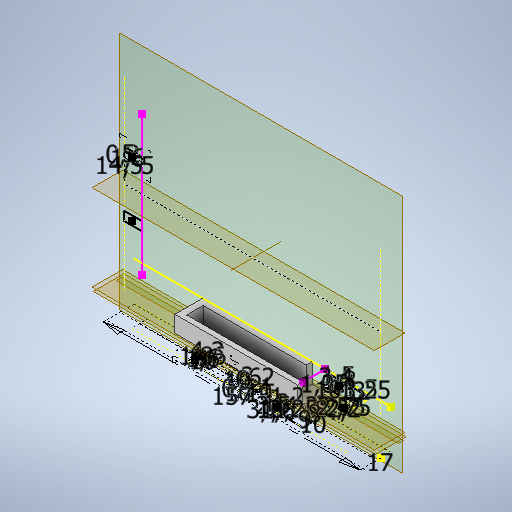
# Autodesk Inventor part: up_part
Saved by Autodesk Inventor 2025 (Build 290162000, 162)
## iProperties
Created: 2026-07-31
Part Number: up_part
Material: Типовые
Document SubType Name: Modeling
Designer: garin
Density: 1 g/cm^3
Appearance: По умолчанию
Author: garin
Autodesk Inventor part; units mm, degrees
ref_plane "YZ Plane" through (0, 0, 0) normal (1, 0, 0) x (0, 1, 0)
ref_plane "XZ Plane" through (0, 0, 0) normal (0, 1, 0) x (-1, 0, 0)
ref_plane "XY Plane" through (0, 0, 0) normal (0, 0, 1) x (1, 0, 0)
sketch "Эскиз1" plane through (0, 0, 0) normal (0, 0, 1) x (1, 0, 0)
  line L0 (0, 0) -> (-157, 0)
  line L1 (-157, 0) -> (-157, 133.4)
  line L2 (-157, 133.4) -> (0, 133.4)
  line L3 (0, 133.4) -> (0, 0)
  line L4 (-157, 66.7) -> (0, 66.7) construction
  line L5 (-78.5, 0) -> (-78.5, 133.4) construction
  line L6 (-11, 24.1) -> (-146, 24.1)
  line L7 (-146, 24.1) -> (-146, 109.3)
  line L8 (-146, 109.3) -> (-11, 109.3)
  line L9 (-11, 109.3) -> (-11, 24.1)
  line L10 (-11, 24.1) -> (-146, 109.3) construction
  line L11 (-146, 24.1) -> (-11, 109.3) construction
  line L12 (0, 0) -> (-2, 0) construction
  line L13 (-2, 0) -> (-2, 54.105) construction
  line L14 (-2, 54.105) -> (0, 54.105) construction
  line L15 (0, 54.105) -> (0, 0) construction
  line L16 (-2, 54.105) -> (-2, 74.935)
  line L17 (-2, 74.935) -> (-11, 74.935)
  line L18 (-2, 54.105) -> (-11, 54.105)
  line L19 (-157, 133.4) -> (-137, 133.4) construction
  line L20 (-157, 110.4) -> (-157, 133.4) construction
  line L21 (-157, 0) -> (-140, 0)
  line L22 (-140, 0) -> (-140, 22)
  line L23 (-140, 22) -> (-157, 22)
  line L24 (-157, 22) -> (-157, 0)
  line L25 (-157, 0) -> (-140, 0)
  line L26 (-140, 0) -> (-140, 6.5)
  line L27 (-140, 6.5) -> (-157, 6.5)
  line L28 (-157, 6.5) -> (-157, 0)
  line L29 (-140, 133.4) -> (-140, 111.4)
  line L30 (-140, 111.4) -> (-157, 111.4)
  line L31 (-140, 126.9) -> (-157, 126.9)
  line L32 (-17, 0) -> (-17, 22)
  line L33 (-17, 22) -> (0, 22)
  line L34 (-17, 6.5) -> (0, 6.5)
  line L35 (-17, 111.4) -> (0, 111.4)
  line L36 (-17, 126.9) -> (0, 126.9)
  line L37 (-17, 133.4) -> (-17, 111.4)
  line L38 (-146, 109.3) -> (-149, 109.3)
  line L39 (-149, 109.3) -> (-149, 24.1)
  line L40 (-149, 24.1) -> (-146, 24.1)
  line L41 (-146, 24.1) -> (-146, 109.3)
  point P0 (-78.5, 66.7)
  point P1 (0, 111.4)
  point P2 (0, 126.9)
  point P3 (-17, 126.9)
  point P4 (-140, 126.9)
  point P5 (0, 6.5)
  dimension "d0" = 157
  dimension "d1" = 133.4
  dimension "d2" = 135
  dimension "d3" = 85.2
  dimension "d20" = 2
  dimension "d21" = 54.105
  dimension "d22" = 20.83
  dimension "d75" = 17
  dimension "d76" = 22
  dimension "d77" = 17
  dimension "d78" = 6.5
  dimension "d151" = 3
  dimension "d152" = 85.2
  constraints: 84 end point, 15 symmetric about line, 12 parallel, 8 perpendicular, 7 horizontal, 7 midpoint, 2 point on line, 1 vertical
  measures "d0" distance of L1.end L2.end
  measures "d1" distance of L0.end L1.end
  measures "d2" distance of L7.end L8.end
  measures "d3" distance of L6.end L7.end
  measures "d20" distance of L13.end L14.end
  measures "d21" distance of L12.end L13.end
  measures "d22" distance of L13.end L16.end
  measures "d75" distance of L23.end L22.end
  measures "d76" distance of L22.end L21.end
  measures "d77" distance of L27.end L26.end
  measures "d78" distance of L26.end L25.end
  measures "d151" distance of L40.end L39.end
  measures "d152" distance of L39.end L38.end
extrude "Выдавливание1" add sketch "Эскиз1" along normal blind 17 contours L0 L32 L34 L3 | L0 L22 L23 L1 L30 L29 L2 L37 L35 L3 L33 L32 | L34 L32 L33 L3 | L0 L1 L27 L22 | L27 L1 L23 L22 | L35 L37 L36 L3 | L36 L37 L2 L3 | L1 L31 L29 L30 | L1 L2 L29 L31 | L9 L17 L16 L18
chamfer "Фаска1" distance 14 angle 45 2 edges at (-78.5, 0, 17) (-78.5, 133.4, 17)
chamfer "Фаска2" distance 5 angle 45 2 edges at (-157, 66.7, 17) (0, 66.7, 17)
sketch "Эскиз2" plane through (-157, 0, 3) normal (0, -0.7071068, 0.7071068) x (1, 0, 0)
  line L0 (0, -2.1213) -> (157, -2.1213) projected
  line L1 (0, -2.1213) -> (157, -2.1213)
  line L2 (157, -2.1213) -> (157, 18.3787)
  line L3 (157, 18.3787) -> (0, 18.3787)
  line L4 (0, 18.3787) -> (0, -2.1213)
  line L5 (78.5, 18.3787) -> (78.5, -2.1213) construction
  line L6 (0, 8.1287) -> (157, 8.1287) construction
  line L7 (154, 1.1287) -> (3, 1.1287) construction
  line L8 (3, 1.1287) -> (3, 15.1287) construction
  line L9 (3, 15.1287) -> (154, 15.1287) construction
  line L10 (154, 15.1287) -> (154, 1.1287) construction
  line L11 (154, 1.1287) -> (3, 15.1287) construction
  line L12 (3, 1.1287) -> (154, 15.1287) construction
  line L13 (3, 15.1287) -> (12, 15.1287) construction
  line L14 (12, 15.1287) -> (3, 2.4008)
  line L15 (0, 12.7279) -> (5, 19.799) construction
  line L16 (145, 15.1287) -> (154, 2.4008)
  line L17 (12, 15.1287) -> (145, 15.1287)
  line L18 (11, 14.92) -> (11, 26.9408) projected
  line L19 (154, 2.4008) -> (154, 1.1287)
  line L20 (154, 1.1287) -> (3, 1.1287)
  line L21 (3, 2.4008) -> (3, 1.1287)
  line L22 (5.9642, 3.1287) -> (13.0353, 13.1287)
  line L23 (13.0353, 13.1287) -> (143.9647, 13.1287)
  line L24 (143.9647, 13.1287) -> (151.0358, 3.1287)
  line L25 (151.0358, 3.1287) -> (5.9642, 3.1287)
  point P0 (78.5, 8.1287)
  dimension "d12" = 157
  dimension "d13" = 20.5
  dimension "d14" = 151
  dimension "d15" = 14
  dimension "d16" = 9
  dimension "d17" = 2
  constraints: 46 end point, 7 midpoint, 5 parallel, 5 perpendicular, 2 horizontal, 2 point on line, 2 symmetric about line, 1 collinear, 3 other
  measures "d12" distance of L3.end L2.end
  measures "d13" distance of L2.end L1.end
  measures "d14" distance of L8.end L9.end
  measures "d15" distance of L7.end L8.end
  measures "d16" distance of L8.end L13.end
  measures "d17" distance between parallel lines of L14 L22
extrude "Выдавливание2" cut sketch "Эскиз2" against normal blind 1 contours L17 L16 L19 L20 L21 L14
ref_plane "РабПлоскость1" through (-157, 66.7, 0) normal (0, 1, 0) x (1, 0, 0)
mirror "Зеркальное отражение1" about plane through (-157, 66.7, 0) normal (0, 1, 0) of "Выдавливание2"
extrude "Выдавливание3" cut sketch "Эскиз1" along normal blind 11.1 contours L9 L17 L16 L18
sketch "Эскиз3" plane through (-157, 0, 0) normal (0, -1, 0) x (1, 0, 0)
  line L0 (0, 0) -> (157, 0) construction
  line L1 (0, 0) -> (157, 0) construction
  line L2 (157, 0) -> (157, 17) construction
  line L3 (157, 17) -> (0, 17) construction
  line L4 (0, 17) -> (0, 0) construction
  line L5 (78.5, 17) -> (78.5, 0) construction
  line L6 (0, 8.5) -> (157, 8.5) construction
  line L7 (145, 13.6976) -> (12, 13.6976) construction
  line L8 (12, 13.6976) -> (12, 3.7981) construction
  line L9 (3, 3.7981) -> (154, 3.7981) construction
  line L10 (12, 8.7478) -> (78.5, 8.7478) construction
  line L11 (12, 8.7478) -> (78.5, 8.7478) construction
  line L12 (83.5, 3.7478) -> (73.5, 3.7478)
  line L13 (73.5, 3.7478) -> (73.5, 13.7478)
  line L14 (73.5, 13.7478) -> (83.5, 13.7478)
  line L15 (83.5, 13.7478) -> (83.5, 3.7478)
  line L16 (83.5, 3.7478) -> (73.5, 13.7478) construction
  line L17 (73.5, 3.7478) -> (83.5, 13.7478) construction
  line L18 (46.5, 13.2478) -> (108.5, 13.2478) construction
  line L19 (108.5, 13.2478) -> (108.5, 4.2478) construction
  line L20 (108.5, 4.2478) -> (46.5, 4.2478) construction
  line L21 (46.5, 4.2478) -> (46.5, 13.2478) construction
  line L22 (46.5, 13.2478) -> (108.5, 4.2478) construction
  line L23 (108.5, 13.2478) -> (46.5, 4.2478) construction
  line L24 (109, 13.7478) -> (46, 13.7478)
  line L25 (46, 13.7478) -> (46, 3.7478)
  line L26 (46, 3.7478) -> (109, 3.7478)
  line L27 (109, 3.7478) -> (109, 13.7478)
  line L28 (46.5, 8.7478) -> (48.3, 8.7478) construction
  line L29 (48.3, 6.7478) -> (48.3, 10.7478) construction
  circle A0 centre (48.3, 10.7478) radius 0.8
  circle A1 centre (48.3, 6.7478) radius 0.8
  line L30 (109, 13.7478) -> (117, 13.7478)
  line L31 (117, 13.7478) -> (117, 3.7478)
  line L32 (117, 3.7478) -> (109, 3.7478)
  line L33 (109, 3.7478) -> (109, 13.7478)
  line L34 (108.5, 13.2478) -> (98.25, 13.2478) construction
  line L35 (98.25, 13.2478) -> (98.25, 10.7478) construction
  line L36 (98.25, 10.7478) -> (108.5, 10.7478) construction
  line L37 (108.5, 10.7478) -> (108.5, 13.2478) construction
  circle A2 centre (98.25, 10.7478) radius 0.8
  line L38 (78.5, 8.7478) -> (77.5, 8.7478) construction
  line L39 (97.45, 10.7478) -> (97.45, 13.7478) construction
  line L40 (97.45, 13.7478) -> (96.25, 13.7478) construction
  line L41 (96.25, 13.7478) -> (96.25, 3.7478)
  line L42 (96.25, 3.7478) -> (97.45, 3.7478) construction
  line L43 (97.45, 3.7478) -> (97.45, 13.7478) construction
  line L44 (83.5, 13.7478) -> (84.5, 13.7478) construction
  line L45 (84.5, 13.7478) -> (84.5, 3.7478)
  line L46 (84.5, 3.7478) -> (83.5, 3.7478) construction
  line L47 (83.5, 3.7478) -> (83.5, 13.7478) construction
  line L48 (73.5, 13.7478) -> (71.5, 13.7478) construction
  line L49 (71.5, 13.7478) -> (71.5, 3.7478)
  line L50 (71.5, 3.7478) -> (73.5, 3.7478) construction
  line L51 (73.5, 3.7478) -> (73.5, 13.7478) construction
  line L52 (46, 13.7478) -> (50.3, 13.7478) construction
  line L53 (50.3, 13.7478) -> (50.3, 3.7478)
  line L54 (50.3, 3.7478) -> (46, 3.7478) construction
  line L55 (46, 3.7478) -> (46, 13.7478) construction
  line L56 (117, 3.7478) -> (109, 3.7478)
  line L57 (109, 3.7478) -> (109, -0.5022)
  line L58 (109, -0.5022) -> (117, -0.5022)
  line L59 (117, -0.5022) -> (117, 3.7478)
  line L60 (99.05, 10.7478) -> (99.05, 13.2478) construction
  line L61 (99.05, 13.2478) -> (100.25, 13.2478) construction
  line L62 (100.25, 13.2478) -> (100.25, 3.7478)
  circle A3 centre (98.25, 10.7478) radius 1.6
  line L63 (99.85, 10.7478) -> (99.85, 13.7478)
  line L64 (96.65, 10.7478) -> (96.65, 13.7478)
  line L65 (100.25, 13.2478) -> (100.25, 13.7478)
  point P0 (84.5, 13.7478)
  point P1 (84.5, 3.7478)
  point P2 (96.25, 3.7478)
  point P3 (96.25, 13.7478)
  point P4 (50.3, 3.7478)
  point P5 (71.5, 3.7478)
  point P6 (71.5, 13.7478)
  point P7 (96.65, 13.7478)
  point P8 (73.5, 3.7478)
  point P9 (83.5, 3.7478)
  dimension "d25" = 157
  dimension "d26" = 17
  dimension "d28" = 10
  dimension "d29" = 10
  dimension "d30" = 62
  dimension "d31" = 9
  dimension "d32" = 0.5
  dimension "d33" = 1.8
  dimension "d34" = 4
  dimension "d35" = 1.6
  dimension "d36" = 1.6
  dimension "d37" = 8
  dimension "d38" = 10
  dimension "d39" = 10.25
  dimension "d40" = 2.5
  dimension "d41" = 1.6
  dimension "d42" = 1
  dimension "d44" = 1.2
  dimension "d45" = 10
  dimension "d46" = 1
  dimension "d47" = 10
  dimension "d48" = 2
  dimension "d49" = 10
  dimension "d50" = 4.3
  dimension "d51" = 10
  dimension "d63" = 8
  dimension "d64" = 4.25
  dimension "d210" = 1.2
  dimension "d211" = 3.2
  constraints: 126 end point, 23 parallel, 17 point on line, 16 perpendicular, 12 horizontal, 11 midpoint, 4 centre point, 4 coincident, 4 point on circle, 4 tangent, 2 vertical, 1 collinear, 3 other
  measures "d25" distance of L3.end L2.end
  measures "d26" distance of L2.end L1.end
  measures "d28" distance of L13.end L14.end
  measures "d29" distance of L12.end L13.end
  measures "d30" distance of L19.end L20.end
  measures "d31" distance of L18.end L19.end
  measures "d32" distance between parallel lines of L18 L24
  measures "d33" distance of L28.end L28.start
  measures "d34" distance of L29.start L29.end
  measures "d35" diameter of A0
  measures "d36" diameter of A1
  measures "d37" distance of L31.end L32.end
  measures "d38" distance of L30.end L31.end
  measures "d39" distance of L36.end L35.end
  measures "d40" distance of L35.end L34.end
  measures "d41" diameter of A2
  measures "d42" distance of L11.end L38.end
  measures "d44" distance of L42.end L41.end
  measures "d45" distance of L41.end L40.end
  measures "d46" distance of L45.end L46.end
  measures "d47" distance of L44.end L45.end
  measures "d48" distance of L50.end L49.end
  measures "d49" distance of L49.end L48.end
  measures "d50" distance of L53.end L54.end
  measures "d51" distance of L52.end L53.end
  measures "d63" distance of L58.end L57.end
  measures "d64" distance of L57.end L56.end
  measures "d210" distance of L60.end L61.end
  measures "d211" diameter of A3
extrude "Выдавливание4" cut sketch "Эскиз3" along normal blind 25 from surface at -24.1 contours L12 L13 L14 L15
ref_plane "РабПлоскость4" through (-145, 11.4047, 12.9905) normal (0, 1, 0) x (1, 0, 0)
ref_plane "РабПлоскость5" through (-145, 14.2047, 12.9905) normal (0, 1, 0) x (1, 0, 0)
extrude "Выдавливание6" cut sketch "Эскиз3" against normal blind 10 from surface at -14.2047 contours L12 L13 L14 L15 | L15 L24 L45 L26 | L26 L49 L24 L13 | L45 L24 L41 L26 | L26 L53 L24 L49 | L41 L24 L64 A3 L63 L65 L62 L26 | L26 L25 L24 L53 | L62 L65 L24 L27 L26 | L24 L63 A3 L64 | A3 | A0 | A1 | A2
extrude "Выдавливание7" cut sketch "Эскиз3" along normal blind 3 from surface at -14.2047 contours A0 | A1 | A2
extrude "Выдавливание8" cut sketch "Эскиз3" along normal blind 2 from surface at -14.2047 contours L15 L24 L45 L26 | L26 L49 L24 L13 | L45 L24 L41 L26 | L26 L53 L24 L49 | L41 L24 L64 A3 L63 L65 L62 L26 | L62 L65 L24 L27 L26
pattern_circular "Круговой массив1" count 2 over 360 about axis through (-78.5, 66.7, 0) along (0, 0, -1) of "Выдавливание4", "Выдавливание8", "Выдавливание6", "Выдавливание7"
chamfer "Фаска3" distance 2 angle 45 1 edges at (-2, 64.52, 11.1)
sketch "Эскиз5" plane through (0, 0, 0) normal (1, 0, 0) x (0, 0, -1)
  line L0 (-12, 9) -> (-12, 124.4) projected
  line L1 (-3, 0) -> (-12, 9) projected
  line L2 (0, 0) -> (-3, 0) projected
  line L3 (0, 0) -> (0, 133.4) projected
  line L4 (0, 133.4) -> (-3, 133.4) projected
  line L5 (-12, 124.4) -> (-3, 133.4) projected
  line L6 (-11, 123.9858) -> (-11, 9.4142)
  line L7 (-11, 9.4142) -> (-2.5858, 1)
  line L8 (-2.5858, 1) -> (-1, 1)
  line L9 (-1, 1) -> (-1, 132.4)
  line L10 (-1, 132.4) -> (-2.5858, 132.4)
  line L11 (-2.5858, 132.4) -> (-11, 123.9858)
  line L12 (-10, 9.8284) -> (-10, 123.5716)
  line L13 (-10, 123.5716) -> (-2, 131.5716)
  line L14 (-2, 131.5716) -> (-2, 1.8284)
  line L15 (-2, 1.8284) -> (-10, 9.8284)
  dimension "d81" = 1
  dimension "d82" = 1
  constraints: 20 end point, 8 other
  measures "d81" distance between parallel lines of L0 L6
  measures "d82" distance between parallel lines of L6 L12
extrude "Выдавливание11" cut sketch "Эскиз1" along normal blind 7 contours L34 L32 L33 L3 | L27 L1 L23 L22 | L35 L37 L36 L3 | L1 L31 L29 L30
extrude "Выдавливание12" cut sketch "Эскиз5" against normal blind 1 contours L11 L10 L9 L8 L7 L6 | L12 L13 L14 L15
chamfer "Фаска4" distance 1 angle 45 4 edges at (-9, 6.5, 7) (-9, 126.9, 7) (-148.5, 126.9, 7) (-148.5, 6.5, 7)
ref_plane "РабПлоскость6" through (-78.5, 22, 0) normal (1, 0, 0) x (0, 0, -1)
mirror "Зеркальное отражение3" about plane through (-78.5, 22, 0) normal (1, 0, 0) of "Выдавливание12"
ref_plane "РабПлоскость7" through (0, 0, 6) normal (0, 0, 1) x (1, 0, 0)
sketch "Эскиз6" plane through (0, 0, 6) normal (0, 0, 1) x (1, 0, 0)
  line L0 (0, 111.4) -> (0, 22) construction
  line L1 (0, 66.7) -> (-157, 66.7) construction
  line L2 (-157, 124.4) -> (-157, 9) construction
  line L3 (-157, 66.7) -> (-157, 81.2) construction
  line L4 (-146, 24.1) -> (-146, 109.3) construction
  line L5 (-157, 81.2) -> (-146, 81.2) construction
  line L6 (-146, 81.2) -> (-146, 86.2) construction
  line L7 (-146, 86.2) -> (-157, 86.2) construction
  line L8 (-157, 86.2) -> (-157, 81.2) construction
  line L9 (-157, 83.7) -> (-146, 83.7) construction
  line L10 (-157, 83.7) -> (-152, 83.7) construction
  circle A0 centre (-152, 83.7) radius 0.8
  circle A1 centre (-152, 49.7) radius 0.8
  line L11 (-157, 81.2) -> (-157, 81) construction
  line L12 (-157, 81) -> (-146, 81)
  line L13 (-157, 86.4) -> (-146, 86.4)
  line L14 (-146, 86.4) -> (-146, 81)
  line L15 (-146, 24.1) -> (-146, 109.3) projected
  line L16 (-157, 81) -> (-157, 86.4)
  line L17 (-157, 52.4) -> (-146, 52.4)
  line L18 (-157, 47) -> (-146, 47)
  line L19 (-146, 47) -> (-146, 52.4)
  line L20 (-157, 52.4) -> (-157, 47)
  point P0 (0, 0)
  dimension "d91" = 14.5
  dimension "d92" = 5
  dimension "d93" = 5
  dimension "d94" = 1.6
  dimension "d99" = 0.2
  constraints: 34 end point, 7 symmetric about line, 5 point on line, 4 midpoint, 2 centre point, 2 collinear, 2 parallel, 2 perpendicular, 1 coincident, 1 horizontal, 1 other
  measures "d91" distance of L1.end L3.end
  measures "d92" distance of L6.end L5.end
  measures "d93" distance of L9.start L10.end
  measures "d94" diameter of A0
  measures "d99" distance of L3.end L11.end
extrude "Выдавливание13" cut sketch "Эскиз6" along normal blind 4 and the other way blind 6 contours A0 | A1
extrude "Выдавливание14" cut sketch "Эскиз6" along normal mid plane 2.8 contours A0 | A1 | L16 L13 L14 L12 | L18 L20 L17 L15
chamfer "Фаска5" distance 0.9 angle 45 2 edges at (-152.8, 83.7, 0) (-152.8, 49.7, 0)
mirror "Зеркальное отражение4" about plane through (-78.5, 22, 0) normal (1, 0, 0) of "Выдавливание14", "Выдавливание13", "Фаска5"
ref_plane "РабПлоскость8" through (-146, 36.9, 17) normal (0, 1, 0) x (1, 0, 0)
sketch "Эскиз7" plane through (-146, 24.1, 17) normal (0, 1, 0) x (1, 0, 0)
  line L0 (135, 17) -> (135, 0) projected
  line L1 (135, 0) -> (132.25, 0) construction
  line L2 (132.25, 0) -> (132.25, 2.15) construction
  line L3 (132.25, 2.15) -> (135, 2.15) construction
  line L4 (135, 2.15) -> (135, 0) construction
  circle A0 centre (132.25, 2.15) radius 1.1
  circle A1 centre (132.25, 2.15) radius 2.15
  line L5 (132.25, 4.3) -> (135, 4.3)
  line L6 (135, 4.3) -> (135, 0)
  line L7 (132.25, 0) -> (135, 0)
  circle A2 centre (132.25, 2.15) radius 2.5
  point P0 (146, 17)
  dimension "d105" = 2.75
  dimension "d106" = 2.15
  dimension "d107" = 2.2
  dimension "d117" = 5
  constraints: 14 end point, 3 centre point, 3 coincident, 3 equal length, 3 perpendicular, 2 point on circle, 2 tangent, 1 horizontal, 1 point on line
  measures "d105" distance of L2.end L3.end
  measures "d106" distance of L1.end L2.end
  measures "d107" diameter of A0
  measures "d117" diameter of A2
extrude "Выдавливание15" add sketch "Эскиз7" along normal blind 11.6 from surface at 12.8 contours L0 L7 A2 L5 | A2 L7 A1 L5 | A1 picked at (134.6155, 1.9787)
pattern_linear "Прямоуг.массив1" count 3 spacing 24 along (0, 1, 0) of "Выдавливание15"
fillet "Сопряжение2" radius 2 2 edges at (-11, 42.7, 12.7) (-11, 90.7, 12.7)
ref_plane "РабПлоскость10" through (-5, 14, 17) normal (0, 1, 0) x (1, 0, 0)
extrude "Выдавливание16" cut sketch "Эскиз7" against normal blind 20 contours A0
extrude "Выдавливание17" add sketch "Эскиз7" against normal blind 5.9 from surface at -10.1 contours A1
chamfer "Фаска6" distance 1 angle 45 1 edges at (-14.85, 8.1, 14.85)
mirror "Зеркальное отражение5" about plane through (-157, 66.7, 0) normal (0, 1, 0) of "Выдавливание17", "Фаска6", "Выдавливание16"
sketch "Эскиз11" plane through (0, 0, 0) normal (0, 0, -1) x (-1, 0, 0)
  line L0 (149, 24.1) -> (149, 109.3) projected
  line L1 (149, 24.1) -> (143, 24.1)
  line L2 (143, 24.1) -> (143, 30.1)
  line L3 (143, 30.1) -> (149, 30.1)
  line L4 (149, 30.1) -> (149, 24.1)
  line L5 (149, 27.1) -> (143, 27.1) construction
  line L6 (146, 30.1) -> (146, 24.1) construction
  circle A0 centre (146, 27.1) radius 1.25
  line L7 (11, 36.9) -> (11, 24.1) construction
  line L8 (149, 24.1) -> (11, 24.1) construction
  line L9 (80, 24.1) -> (80, 109.3) construction
  line L10 (149, 109.3) -> (11, 109.3) construction
  line L11 (11, 24.1) -> (11, 109.3)
  line L12 (11, 24.1) -> (17, 24.1)
  line L13 (17, 24.1) -> (17, 30.1)
  line L14 (17, 30.1) -> (11, 30.1)
  line L15 (11, 30.1) -> (11, 24.1)
  line L16 (11, 27.1) -> (17, 27.1) construction
  line L17 (14, 30.1) -> (14, 24.1) construction
  circle A1 centre (14, 27.1) radius 1.25
  line L18 (11, 24.1) -> (149, 24.1) construction
  line L19 (149, 66.7) -> (11, 66.7) construction
  line L20 (149, 109.3) -> (143, 109.3)
  line L21 (143, 109.3) -> (143, 103.3)
  line L22 (143, 103.3) -> (149, 103.3)
  line L23 (149, 103.3) -> (149, 109.3)
  line L24 (149, 106.3) -> (143, 106.3) construction
  line L25 (146, 103.3) -> (146, 109.3) construction
  circle A2 centre (146, 106.3) radius 1.25
  line L26 (11, 96.5) -> (11, 109.3) construction
  line L27 (149, 109.3) -> (11, 109.3) construction
  line L28 (11, 109.3) -> (17, 109.3)
  line L29 (17, 109.3) -> (17, 103.3)
  line L30 (17, 103.3) -> (11, 103.3)
  line L31 (11, 103.3) -> (11, 109.3)
  line L32 (11, 106.3) -> (17, 106.3) construction
  line L33 (14, 103.3) -> (14, 109.3) construction
  circle A3 centre (14, 106.3) radius 1.25
  line L34 (11, 109.3) -> (149, 109.3) construction
  point P0 (0, 0)
  dimension "d157" = 6
  dimension "d158" = 6
  dimension "d159" = 2.5
  constraints: 64 end point, 31 symmetric about line, 9 midpoint, 4 centre point, 2 parallel, 2 perpendicular, 1 horizontal, 3 other
  measures "d157" distance of L2.end L3.end
  measures "d158" distance of L1.end L2.end
  measures "d159" diameter of A0
extrude "Выдавливание21" add sketch "Эскиз11" against normal blind 2.8
fillet "Сопряжение5" radius 2 11 edges at (-17, 30.1, 1.4) (-11, 30.1, 1.4) (-17, 109.3, 1.4) (-17, 103.3, 1.4) (-11, 103.3, 1.4) (-149, 103.3, 1.4) (-143, 103.3, 1.4) (-143, 109.3, 1.4) (-149, 30.1, 1.4) (-143, 30.1, 1.4) (-143, 24.1, 1.4)
sketch "Эскиз12" plane through (0, 0, 0) normal (0, 0, -1) x (-1, 0, 0)
  line L0 (11, 54.105) -> (7.5, 54.105)
  line L1 (7.5, 54.105) -> (7.5, 46.605)
  line L2 (7.5, 46.605) -> (11, 46.605)
  line L3 (11, 46.605) -> (11, 54.105)
  point P0 (0, 0)
  dimension "d163" = 3.5
  dimension "d164" = 7.5
  constraints: 8 end point, 2 parallel, 1 horizontal, 1 perpendicular
  measures "d163" distance of L2.end L1.end
  measures "d164" distance of L1.end L0.end
extrude "Выдавливание22" cut sketch "Эскиз12" against normal blind 3
sketch "Эскиз13" plane through (-149, 24.1, 17) normal (0, 1, 0) x (1, 0, 0)
  circle A0 centre (135.25, 2.15) radius 1.1 projected
  line L0 (135.25, 2.15) -> (135.25, 17) construction
  line L1 (-8, 17) -> (149, 17) projected
  line L2 (135.25, 2.15) -> (122.25, 2.15) construction
  line L3 (122.25, 2.15) -> (122.25, 12.15) construction
  line L4 (122.25, 12.15) -> (135.25, 12.15) construction
  line L5 (135.25, 12.15) -> (135.25, 2.15) construction
  circle A1 centre (122.25, 12.15) radius 1.7
  line L6 (126.25, 7.3) -> (118.25, 7.3)
  line L7 (118.25, 7.3) -> (118.25, 17)
  line L8 (118.25, 17) -> (126.25, 17)
  line L9 (126.25, 17) -> (126.25, 7.3)
  line L10 (126.25, 7.3) -> (118.25, 17) construction
  line L11 (118.25, 7.3) -> (126.25, 17) construction
  line L12 (126.25, 7.3) -> (118.25, 7.3)
  line L13 (118.25, 7.3) -> (118.25, 8.35)
  line L14 (118.25, 8.35) -> (126.25, 8.35)
  line L15 (126.25, 8.35) -> (126.25, 7.3)
  line L16 (126.25, 17) -> (118.25, 17)
  line L17 (118.25, 17) -> (118.25, 15.5)
  line L18 (118.25, 15.5) -> (126.25, 15.5)
  line L19 (126.25, 15.5) -> (126.25, 17)
  line L20 (126.25, 15.5) -> (135.25, 15.5)
  line L21 (135.25, 15.5) -> (135.25, 17)
  line L22 (135.25, 17) -> (126.25, 17)
  line L23 (126.25, 17) -> (126.25, 15.5)
  line L24 (109, 17) -> (109, 3.1539) projected
  line L25 (118.25, 15.5) -> (109, 15.5)
  line L26 (109, 15.5) -> (109, 17)
  line L27 (109, 17) -> (118.25, 17)
  line L28 (118.25, 17) -> (118.25, 15.5)
  line L29 (135.25, 15.5) -> (132, 15.5)
  line L30 (132, 15.5) -> (132, 17)
  line L31 (132, 17) -> (135.25, 17)
  line L32 (135.25, 17) -> (135.25, 15.5)
  point P0 (132, 15.5)
  point P1 (132, 17)
  dimension "d167" = 13
  dimension "d168" = 10
  dimension "d169" = 3.4
  dimension "d170" = 8
  dimension "d175" = 1.05
  dimension "d197" = 1.5
  dimension "d203" = 3.25
  dimension "d204" = 1.5
  constraints: 62 end point, 14 parallel, 7 horizontal, 7 perpendicular, 4 point on line, 2 midpoint, 1 centre point, 1 coincident, 1 vertical
  measures "d167" distance of L3.end L4.end
  measures "d168" distance of L2.end L3.end
  measures "d169" diameter of A1
  measures "d170" distance of L7.end L8.end
  measures "d175" distance of L12.end L13.end
  measures "d197" distance of L17.end L16.end
  measures "d203" distance of L30.end L31.end
  measures "d204" distance of L29.end L30.end
extrude "Выдавливание23" add sketch "Эскиз13" along normal blind 5 contours L1 L9 L18 L7 | L18 L9 L14 L7
sketch "Эскиз15" plane through (0, 0, 0) normal (0, 0, -1) x (-1, 0, 0)
  line L0 (0, 0) -> (0, 6.5) projected
  line L1 (0, 0) -> (40, 0)
  line L2 (40, 0) -> (40, 6.5)
  line L3 (40, 6.5) -> (0, 6.5)
  line L4 (0, 6.5) -> (0, 0)
  line L5 (17, 22) -> (17, 6.5) projected
  line L6 (17, 6.5) -> (33, 6.5)
  line L7 (33, 6.5) -> (33, 12.5)
  line L8 (33, 12.5) -> (17, 12.5)
  line L9 (17, 12.5) -> (17, 6.5)
  line L10 (0, 9) -> (0, 124.4) construction
  line L11 (0, 66.7) -> (157, 66.7) construction
  line L12 (157, 124.4) -> (157, 9) construction
  line L13 (0, 133.4) -> (157, 133.4) construction
  line L14 (78.5, 133.4) -> (78.5, 0) construction
  line L15 (157, 0) -> (0, 0) construction
  line L16 (0, 133.4) -> (0, 126.9)
  line L17 (0, 133.4) -> (40, 133.4)
  line L18 (40, 133.4) -> (40, 126.9)
  line L19 (40, 126.9) -> (0, 126.9)
  line L20 (0, 126.9) -> (0, 133.4)
  line L21 (17, 126.9) -> (33, 126.9)
  line L22 (33, 126.9) -> (33, 120.9)
  line L23 (33, 120.9) -> (17, 120.9)
  line L24 (17, 120.9) -> (17, 126.9)
  line L25 (0, 124.4) -> (0, 9) construction
  line L26 (157, 133.4) -> (0, 133.4) construction
  line L27 (157, 0) -> (157, 6.5)
  line L28 (157, 0) -> (117, 0)
  line L29 (117, 0) -> (117, 6.5)
  line L30 (117, 6.5) -> (157, 6.5)
  line L31 (157, 6.5) -> (157, 0)
  line L32 (140, 6.5) -> (124, 6.5)
  line L33 (124, 6.5) -> (124, 12.5)
  line L34 (124, 12.5) -> (140, 12.5)
  line L35 (140, 12.5) -> (140, 6.5)
  line L36 (157, 9) -> (157, 124.4) construction
  line L37 (0, 0) -> (157, 0) construction
  line L38 (117, 133.4) -> (117, 126.9)
  line L39 (124, 126.9) -> (124, 120.9)
  line L40 (124, 120.9) -> (140, 120.9)
  line L41 (140, 126.9) -> (124, 126.9)
  line L42 (140, 120.9) -> (140, 126.9)
  line L43 (157, 133.4) -> (157, 126.9)
  line L44 (157, 133.4) -> (117, 133.4)
  line L45 (157, 126.9) -> (157, 133.4)
  line L46 (117, 126.9) -> (157, 126.9)
  line L47 (157, 124.4) -> (157, 9) construction
  line L48 (124, 120.9) -> (117, 120.9)
  line L49 (117, 120.9) -> (117, 126.9)
  line L50 (117, 126.9) -> (124, 126.9)
  line L51 (124, 126.9) -> (124, 120.9)
  line L52 (124, 12.5) -> (117, 12.5)
  line L53 (117, 12.5) -> (117, 6.5)
  line L54 (117, 6.5) -> (124, 6.5)
  line L55 (124, 6.5) -> (124, 12.5)
  line L56 (140, 120.9) -> (134, 120.9)
  line L57 (134, 120.9) -> (134, 111.4)
  line L58 (134, 111.4) -> (140, 111.4)
  line L59 (140, 111.4) -> (140, 120.9)
  line L60 (117, 6.5) -> (113.5, 6.5)
  line L61 (113.5, 6.5) -> (113.5, 0)
  line L62 (113.5, 0) -> (117, 0)
  line L63 (117, 0) -> (117, 6.5)
  line L64 (117, 133.4) -> (117, 126.9)
  line L65 (117, 126.9) -> (113.5, 126.9)
  line L66 (113.5, 126.9) -> (113.5, 133.4)
  line L67 (113.5, 133.4) -> (117, 133.4)
  line L68 (117, 133.4) -> (117, 126.9)
  line L69 (117, 120.9) -> (113.5, 120.9)
  line L70 (113.5, 120.9) -> (113.5, 126.9)
  line L71 (113.5, 126.9) -> (117, 126.9)
  line L72 (117, 126.9) -> (117, 120.9)
  dimension "d176" = 40
  dimension "d177" = 6.5
  dimension "d178" = 16
  dimension "d179" = 6
  dimension "d182" = 6
  dimension "d183" = 9.5
  dimension "d184" = 3.5
  constraints: 134 end point, 36 symmetric about line, 14 parallel, 7 horizontal, 7 perpendicular, 4 midpoint, 1 point on line
  measures "d176" distance of L3.end L2.end
  measures "d177" distance of L2.end L1.end
  measures "d178" distance of L8.end L7.end
  measures "d179" distance of L7.end L6.end
  measures "d182" distance of L58.end L57.end
  measures "d183" distance of L57.end L56.end
  measures "d184" distance of L62.end L61.end
extrude "Выдавливание24" cut sketch "Эскиз15" against normal blind 2.5
sketch "Эскиз16" plane through (0, 0, 0) normal (0, 0, -1) x (-1, 0, 0)
  line L0 (17, 6.5) -> (17, 12.5) projected
  line L1 (17, 6.5) -> (40, 6.5)
  line L2 (40, 6.5) -> (40, 21.5)
  line L3 (40, 21.5) -> (17, 21.5)
  line L4 (17, 21.5) -> (17, 6.5)
  line L5 (40, 6.5) -> (17, 6.5)
  line L6 (17, 6.5) -> (17, 12.5)
  line L7 (17, 12.5) -> (40, 12.5)
  line L8 (40, 12.5) -> (40, 6.5)
  point P0 (0, 0)
  point P1 (40, 12.5)
  dimension "d185" = 23
  dimension "d186" = 15
  dimension "d189" = 23
  dimension "d190" = 6
  constraints: 16 end point, 4 parallel, 2 horizontal, 2 perpendicular
  measures "d185" distance of L3.end L2.end
  measures "d186" distance of L2.end L1.end
  measures "d189" distance of L0.end L7.end
  measures "d190" distance of L5.end L0.end
extrude "Выдавливание25" cut sketch "Эскиз16" against normal blind 9 contours L4 L3 L2 L7
sketch "Эскиз17" plane through (0, 0, 0) normal (0, 0, -1) x (-1, 0, 0)
  line L0 (85.15, 121.15) -> (85.15, 122.75) construction
  line L1 (82.2, 122.75) -> (82.2, 121.15) construction
  line L2 (85.15, 122.75) -> (86.15, 122.75) construction
  line L3 (86.15, 122.75) -> (86.15, 123.75) construction
  line L4 (86.15, 123.75) -> (85.15, 123.75) construction
  line L5 (85.15, 123.75) -> (85.15, 122.75) construction
  line L6 (86.15, 123.75) -> (81.2, 123.75)
  line L7 (81.2, 123.75) -> (81.2, 120.15)
  line L8 (81.2, 120.15) -> (86.15, 120.15)
  line L9 (86.15, 120.15) -> (86.15, 123.75)
  point P0 (0, 0)
  dimension "d191" = 1
  dimension "d192" = 1
  dimension "d193" = 4.95
  dimension "d194" = 3.6
  constraints: 16 end point, 4 parallel, 2 horizontal, 2 perpendicular
  measures "d191" distance of L4.end L3.end
  measures "d192" distance of L3.end L2.end
  measures "d193" distance of L8.end L7.end
  measures "d194" distance of L7.end L6.end
extrude "Выдавливание26" cut sketch "Эскиз17" against normal blind 1
extrude "Выдавливание27" cut sketch "Эскиз13" along normal blind 5 and the other way blind 3 contours L1 L7 L25 L24 | L1 L9 L18 L7 | L1 L30 L20 L9
fillet "Сопряжение8" radius 2 4 edges at (-22.75, 24.1, 5.075) (-30.75, 24.1, 5.075) (-30.75, 26.6, 8.65) (-22.75, 26.6, 8.65)
ref_plane "РабПлоскость11" through (-157, 10.16, 3) normal (0, -1, 0) x (1, 0, 0)
sketch "Эскиз18" plane through (-157, 10.16, 3) normal (0, -1, 0) x (1, 0, 0)
  circle A0 centre (78.5, 5.7478) radius 1.3132 projected
  line L0 (76, 3.2478) -> (81, 3.2478)
  line L1 (81, 3.2478) -> (81, 8.2478)
  line L2 (81, 8.2478) -> (76, 8.2478)
  line L3 (76, 8.2478) -> (76, 3.2478)
  line L4 (76, 3.2478) -> (81, 8.2478) construction
  line L5 (81, 3.2478) -> (76, 8.2478) construction
  point P0 (157, -3)
  dimension "d206" = 5
  dimension "d207" = 5
  constraints: 12 end point, 2 midpoint, 2 parallel, 1 horizontal, 1 perpendicular
  measures "d206" distance of L2.end L1.end
  measures "d207" distance of L1.end L0.end
extrude "Выдавливание28" cut sketch "Эскиз18" along normal blind 12 draft 50 contours A0 | L3 L2 L1 L0
extrude "Выдавливание29" cut sketch "Эскиз3" along normal blind 12 from surface at -24.1 contours L62 L65 L24 L27 L26 | L27 L30 L31 L32 | L32 L59 L58 L57
chamfer "Фаска8" distance 0.5 angle 45 4 edges at (-114.25, 11.4061, 12.9891) (-44.1634, 11.4061, 12.9891) (-44.1634, 121.9939, 12.9891) (-114.25, 121.9939, 12.9891)
chamfer "Фаска9" distance 2 angle 45 1 edges at (-28.5, 21.5, 1.5)
ref_plane "РабПлоскость12" through (0, 0, 0.8) normal (0, 0, -1) x (-1, 0, 0)
sketch "Эскиз21" plane through (0, 0, 0.8) normal (0, 0, -1) x (-1, 0, 0)
  line L0 (113.5, 0) -> (93.1082, 0) projected
  line L1 (83.5, 8.0623) -> (87.2478, 4.9174) projected
  line L2 (93.1082, 0) -> (87.2478, 4.9174)
  line L3 (87.2478, 4.9174) -> (69.7522, 4.9174)
  line L4 (69.7522, 4.9174) -> (63.8918, 0)
  line L5 (73.5, 8.0623) -> (69.7522, 4.9174) projected
  line L6 (63.8918, 0) -> (93.1082, 0)
  line L7 (87.2478, 4.9174) -> (85.7158, 6.203)
  line L8 (69.7522, 4.9174) -> (71.2842, 6.203)
  line L9 (71.2842, 6.203) -> (85.7158, 6.203)
  point P0 (0, 0)
  dimension "d223" = 2
  dimension "d224" = 2
  constraints: 14 end point, 2 collinear, 2 point on line, 1 horizontal, 1 parallel
  measures "d223" distance of L1.end L7.end
  measures "d224" distance of L3.end L8.end
extrude "Выдавливание30" add sketch "Эскиз21" along normal blind 0.8
sketch "Эскиз22" plane through (0, 0, 17) normal (0, 0, 1) x (1, 0, 0)
  line L0 (-70.5522, 5.5887) -> (-63.8918, 0) projected
  line L1 (-93.1082, 0) -> (-63.8918, 0) construction
  line L2 (-40, 23.5) -> (-40, 24.1) projected
  line L3 (-40, 24.1) -> (-115, 24.1)
  line L4 (-115, 24.1) -> (-115, 0)
  line L5 (-115, 0) -> (-40, 0)
  line L6 (-40, 0) -> (-40, 24.1)
  point P0 (0, 0)
  dimension "d225" = 75
  dimension "d226" = 24.1
  constraints: 10 end point, 2 horizontal, 2 parallel, 1 perpendicular
  measures "d225" distance of L5.end L4.end
  measures "d226" distance of L4.end L3.end
extrude "Выдавливание31" cut sketch "Эскиз22" against normal blind 100 keep common part
